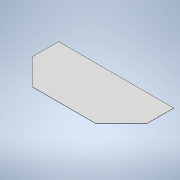
# Autodesk Inventor part: Sensoraufsatz
Saved by Autodesk Inventor 2020 (Build 240168000, 168)
## iProperties
Created: 2020-04-29
Part Number: Sensoraufsatz
Material: Generisch
Document SubType Name: Modeling
Designer: Chris
Density: 1 g/cm^3
Appearance: Vorgabe
Author: Chris
Autodesk Inventor part; units mm, degrees
ref_plane "YZ Plane" through (0, 0, 0) normal (1, 0, 0) x (0, 1, 0)
ref_plane "XZ Plane" through (0, 0, 0) normal (0, 1, 0) x (-1, 0, 0)
ref_plane "XY Plane" through (0, 0, 0) normal (0, 0, 1) x (1, 0, 0)
sketch "Skizze1" plane through (0, 0, 0) normal (0, 1, 0) x (-1, 0, 0)
  line L0 (525, 0) -> (525, 250)
  line L1 (525, 0) -> (775, 0) construction
  line L2 (525, 0) -> (525, 500) construction
  line L3 (525, 500) -> (-475, 500) construction
  line L4 (525, 250) -> (275, 500) construction
  line L5 (525, 250) -> (878.5534, 250) construction
  line L6 (525, 250) -> (275, 500)
  line L7 (525, 0) -> (-575, 0)
  line L8 (525, 0) -> (1625, 0) construction
  line L9 (-575, 0) -> (-575, 250)
  line L10 (-575, 250) -> (-325, 500)
  line L11 (-325, 500) -> (275, 500)
  point P0 (0, 0)
  dimension "d1" = 250
  dimension "d2" = 90
  dimension "d3" = 500
  dimension "d4" = 1000
  dimension "d5" = 135
  dimension "d7" = 1100
  dimension "d8" = 180
  dimension "d9" = 250
  dimension "d10" = 135
  constraints: 24 end point, 3 equal length, 3 horizontal, 3 perpendicular, 3 point on line, 1 parallel, 1 vertical
  measures "d1" distance of L0.start L0.end
  measures "d2" angle of L1 L0
  measures "d3" distance of L0.start L2.end
  measures "d4" distance of L2.end L3.end
  measures "d5" angle of L5 L4
  measures "d7" distance of L0.start L7.end
  measures "d8" angle of L7 L8
  measures "d9" distance of L7.end L9.end
  measures "d10" angle of L9 L10
extrude "Extrusion1" add sketch "Skizze1" along normal blind 2
